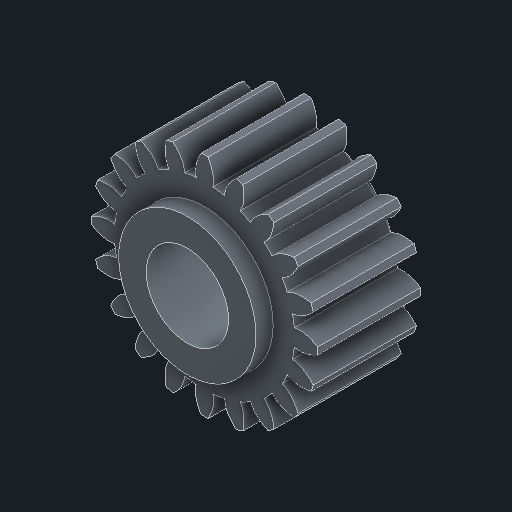
# Autodesk Inventor part: G1
Saved by Autodesk Inventor 2027 (Build 310192000, 192)
## iProperties
Created: 2026-11-10
Part Number: G1
Material: Genérico
Description: Engrenagem G1
Document SubType Name: Modeling
Designer: Bruno Madela
Mass: 9.65709 g
Surface Area: 51.8359 cm^2
Volume: 9.65709 cm^3
Density: 1 g/cm^3
Appearance: Aço
Author: Bruno Madela
Autodesk Inventor part; units mm, degrees
ref_plane "YZ Plane" through (0, 0, 0) normal (1, 0, 0) x (0, 1, 0)
ref_plane "XZ Plane" through (0, 0, 0) normal (0, 1, 0) x (-1, 0, 0)
sketch "Esboço1" plane through (0, 0, 0) normal (0, 0, 1) x (1, 0, 0)
  circle A0 centre (0, 0) radius 10
  dimension "d0" = 20
  constraints: 1 centre point
  measures "d0" diameter of A0
extrude "Extrusão1" add sketch "Esboço1" along normal blind 20
ref_plane "Plano de trabalho1" through (0, 0, 2.5) normal (0, 0, 1) x (1, 0, 0)
sketch "Esboço2" plane through (0, 0, 2.5) normal (0, 0, 1) x (1, 0, 0)
  spline S0 degree 4 poles (13.0677, -1.2247) (13.1346, -1.232) (13.263, -1.2459) (13.4395, -1.2641) (13.6431, -1.283) (13.8156, -1.2967) (13.9593, -1.3052) (14.0776, -1.3089) (14.1764, -1.3079) (14.2635, -1.3028) (14.3466, -1.2941) (14.432, -1.2822) (14.5223, -1.2675) (14.6167, -1.2504) (14.7127, -1.2311) (14.8076, -1.2098) (14.9005, -1.1865) (14.9917, -1.1614) (15.0824, -1.1345) (15.1735, -1.1058) (15.2655, -1.0755) (15.3579, -1.0435) (15.4503, -1.01) (15.5422, -0.9749) (15.6336, -0.9383) (15.7246, -0.9003) (15.8154, -0.8608) (15.9062, -0.8199) (15.9969, -0.7776) (16.0875, -0.734) (16.1779, -0.689) (16.268, -0.6427) (16.3578, -0.5952) (16.4249, -0.5585) (16.4695, -0.5336) (16.4918, -0.5211) knots 0 0 0 0 0 0.03125 0.0625 0.09375 0.125 0.15625 0.1875 0.21875 0.25 0.28125 0.3125 0.34375 0.375 0.40625 0.4375 0.46875 0.5 0.53125 0.5625 0.59375 0.625 0.65625 0.6875 0.71875 0.75 0.78125 0.8125 0.84375 0.875 0.90625 0.9375 0.96875 1 1 1 1 1
  spline S1 degree 4 poles (16.4918, 0.5211) (16.4694, 0.5337) (16.4247, 0.5588) (16.3574, 0.5959) (16.2674, 0.6439) (16.177, 0.6906) (16.0864, 0.736) (15.9956, 0.78) (15.9046, 0.8227) (15.8137, 0.864) (15.7227, 0.9038) (15.6315, 0.9422) (15.5399, 0.9791) (15.4478, 1.0145) (15.3552, 1.0483) (15.2626, 1.0806) (15.1705, 1.1112) (15.0792, 1.1401) (14.9884, 1.1672) (14.897, 1.1926) (14.8041, 1.2161) (14.709, 1.2376) (14.6129, 1.257) (14.5184, 1.2742) (14.4279, 1.289) (14.3423, 1.3011) (14.259, 1.3101) (14.172, 1.3153) (14.0733, 1.3162) (13.9553, 1.3122) (13.8122, 1.3029) (13.6403, 1.2881) (13.4377, 1.2675) (13.262, 1.2478) (13.1343, 1.2327) (13.0677, 1.2247) knots 0 0 0 0 0 0.03125 0.0625 0.09375 0.125 0.15625 0.1875 0.21875 0.25 0.28125 0.3125 0.34375 0.375 0.40625 0.4375 0.46875 0.5 0.53125 0.5625 0.59375 0.625 0.65625 0.6875 0.71875 0.75 0.78125 0.8125 0.84375 0.875 0.90625 0.9375 0.96875 1 1 1 1 1
  spline S2 degree 4 poles (12.8066, 2.8734) (12.8723, 2.8863) (12.9985, 2.9114) (13.1716, 2.9468) (13.3706, 2.9898) (13.5386, 3.0287) (13.6775, 3.0641) (13.7909, 3.0968) (13.8844, 3.1282) (13.9656, 3.1602) (14.0419, 3.1945) (14.1195, 3.2325) (14.201, 3.2746) (14.2857, 3.3202) (14.371, 3.3684) (14.4548, 3.4182) (14.5359, 3.4693) (14.615, 3.5216) (14.693, 3.5756) (14.7709, 3.6313) (14.849, 3.6889) (14.9272, 3.7481) (15.0047, 3.8089) (15.0815, 3.871) (15.1572, 3.9344) (15.2321, 3.9991) (15.3064, 4.0651) (15.3802, 4.1325) (15.4535, 4.2012) (15.5263, 4.2711) (15.5985, 4.3422) (15.6701, 4.4146) (15.7409, 4.4881) (15.7935, 4.544) (15.8283, 4.5817) (15.8456, 4.6007) knots 0 0 0 0 0 0.03125 0.0625 0.09375 0.125 0.15625 0.1875 0.21875 0.25 0.28125 0.3125 0.34375 0.375 0.40625 0.4375 0.46875 0.5 0.53125 0.5625 0.59375 0.625 0.65625 0.6875 0.71875 0.75 0.78125 0.8125 0.84375 0.875 0.90625 0.9375 0.96875 1 1 1 1 1
  spline S3 degree 4 poles (15.5236, 5.5918) (15.4984, 5.5969) (15.4481, 5.607) (15.3727, 5.6214) (15.2723, 5.6393) (15.1719, 5.6558) (15.0717, 5.6709) (14.9717, 5.6847) (14.872, 5.6972) (14.7728, 5.7083) (14.6739, 5.7181) (14.5753, 5.7264) (14.4768, 5.7332) (14.3783, 5.7384) (14.2798, 5.7419) (14.1818, 5.744) (14.0847, 5.7446) (13.9889, 5.7439) (13.8942, 5.7417) (13.7995, 5.7376) (13.7038, 5.7311) (13.6068, 5.7222) (13.5094, 5.711) (13.4141, 5.6981) (13.3235, 5.6842) (13.2383, 5.6693) (13.1564, 5.6521) (13.072, 5.6301) (12.9778, 5.6005) (12.8668, 5.5602) (12.7336, 5.5072) (12.5747, 5.44) (12.3883, 5.3579) (12.2273, 5.2848) (12.1105, 5.2311) (12.0497, 5.2029) knots 0 0 0 0 0 0.03125 0.0625 0.09375 0.125 0.15625 0.1875 0.21875 0.25 0.28125 0.3125 0.34375 0.375 0.40625 0.4375 0.46875 0.5 0.53125 0.5625 0.59375 0.625 0.65625 0.6875 0.71875 0.75 0.78125 0.8125 0.84375 0.875 0.90625 0.9375 0.96875 1 1 1 1 1
  spline S4 degree 4 poles (11.2919, 6.6902) (11.3504, 6.7228) (11.4626, 6.7856) (11.6164, 6.8728) (11.7924, 6.9751) (11.9402, 7.0641) (12.0614, 7.1406) (12.1592, 7.2067) (12.2384, 7.2655) (12.3058, 7.3209) (12.3678, 7.3771) (12.4299, 7.4372) (12.4944, 7.5025) (12.5608, 7.572) (12.6271, 7.6442) (12.6914, 7.7174) (12.7528, 7.7911) (12.8118, 7.8653) (12.8693, 7.9407) (12.9262, 8.0178) (12.9827, 8.0967) (13.0386, 8.1772) (13.0937, 8.259) (13.1474, 8.3418) (13.1998, 8.4255) (13.251, 8.5102) (13.3013, 8.5959) (13.3506, 8.6828) (13.3991, 8.7708) (13.4467, 8.8598) (13.4934, 8.9498) (13.539, 9.0408) (13.5836, 9.1326) (13.6163, 9.2021) (13.6378, 9.2487) (13.6484, 9.2721) knots 0 0 0 0 0 0.03125 0.0625 0.09375 0.125 0.15625 0.1875 0.21875 0.25 0.28125 0.3125 0.34375 0.375 0.40625 0.4375 0.46875 0.5 0.53125 0.5625 0.59375 0.625 0.65625 0.6875 0.71875 0.75 0.78125 0.8125 0.84375 0.875 0.90625 0.9375 0.96875 1 1 1 1 1
  spline S5 degree 4 poles (13.0358, 10.1152) (13.0103, 10.1123) (12.9594, 10.1063) (12.8833, 10.0967) (12.7823, 10.0826) (12.6818, 10.0673) (12.5818, 10.0507) (12.4825, 10.0329) (12.3839, 10.014) (12.2861, 9.9939) (12.1891, 9.9726) (12.0928, 9.9501) (11.9971, 9.926) (11.9018, 9.9005) (11.807, 9.8735) (11.7132, 9.8451) (11.6208, 9.8157) (11.5299, 9.7854) (11.4405, 9.754) (11.3517, 9.7208) (11.2628, 9.6851) (11.1733, 9.6466) (11.0841, 9.6059) (10.9975, 9.5642) (10.9156, 9.5229) (10.8393, 9.4824) (10.7667, 9.4407) (10.6932, 9.3937) (10.6129, 9.3364) (10.5197, 9.2638) (10.4092, 9.1722) (10.2788, 9.0593) (10.1267, 8.9237) (9.996, 8.8045) (9.9014, 8.7173) (9.8522, 8.6718) knots 0 0 0 0 0 0.03125 0.0625 0.09375 0.125 0.15625 0.1875 0.21875 0.25 0.28125 0.3125 0.34375 0.375 0.40625 0.4375 0.46875 0.5 0.53125 0.5625 0.59375 0.625 0.65625 0.6875 0.71875 0.75 0.78125 0.8125 0.84375 0.875 0.90625 0.9375 0.96875 1 1 1 1 1
  spline S6 degree 4 poles (8.6718, 9.8522) (8.7174, 9.9012) (8.8047, 9.9956) (8.9239, 10.126) (9.0596, 10.2778) (9.1727, 10.408) (9.2643, 10.5183) (9.3368, 10.6114) (9.3941, 10.6917) (9.441, 10.7653) (9.4827, 10.8379) (9.5232, 10.9143) (9.5644, 10.9963) (9.606, 11.0829) (9.6468, 11.1721) (9.6853, 11.2616) (9.7209, 11.3506) (9.7541, 11.4394) (9.7855, 11.5289) (9.8158, 11.6198) (9.8452, 11.7123) (9.8735, 11.8062) (9.9006, 11.901) (9.9261, 11.9963) (9.9501, 12.0921) (9.9726, 12.1885) (9.9939, 12.2856) (10.014, 12.3834) (10.0329, 12.4821) (10.0507, 12.5815) (10.0673, 12.6815) (10.0826, 12.7821) (10.0967, 12.8832) (10.1063, 12.9594) (10.1123, 13.0103) (10.1152, 13.0358) knots 0 0 0 0 0 0.03125 0.0625 0.09375 0.125 0.15625 0.1875 0.21875 0.25 0.28125 0.3125 0.34375 0.375 0.40625 0.4375 0.46875 0.5 0.53125 0.5625 0.59375 0.625 0.65625 0.6875 0.71875 0.75 0.78125 0.8125 0.84375 0.875 0.90625 0.9375 0.96875 1 1 1 1 1
  spline S7 degree 4 poles (9.2721, 13.6484) (9.2487, 13.6378) (9.2021, 13.6164) (9.1325, 13.5837) (9.0407, 13.5391) (8.9498, 13.4935) (8.8598, 13.4468) (8.7707, 13.3992) (8.6827, 13.3508) (8.5958, 13.3014) (8.5101, 13.2512) (8.4254, 13.2) (8.3417, 13.1476) (8.2588, 13.0939) (8.177, 13.0389) (8.0965, 12.9829) (8.0176, 12.9264) (7.9405, 12.8695) (7.8651, 12.812) (7.7909, 12.753) (7.7173, 12.6916) (7.644, 12.6274) (7.5718, 12.561) (7.5023, 12.4946) (7.4371, 12.4301) (7.377, 12.368) (7.3208, 12.3059) (7.2654, 12.2385) (7.2067, 12.1592) (7.1406, 12.0614) (7.064, 11.9401) (6.9751, 11.7923) (6.8728, 11.6164) (6.7856, 11.4626) (6.7228, 11.3504) (6.6902, 11.2919) knots 0 0 0 0 0 0.03125 0.0625 0.09375 0.125 0.15625 0.1875 0.21875 0.25 0.28125 0.3125 0.34375 0.375 0.40625 0.4375 0.46875 0.5 0.53125 0.5625 0.59375 0.625 0.65625 0.6875 0.71875 0.75 0.78125 0.8125 0.84375 0.875 0.90625 0.9375 0.96875 1 1 1 1 1
  spline S8 degree 4 poles (5.2029, 12.0497) (5.2311, 12.1104) (5.285, 12.2272) (5.3582, 12.388) (5.4404, 12.5742) (5.5077, 12.733) (5.5608, 12.8662) (5.6011, 12.9771) (5.6307, 13.0713) (5.6526, 13.1557) (5.6698, 13.2376) (5.6848, 13.3228) (5.6986, 13.4135) (5.7115, 13.5088) (5.7227, 13.6062) (5.7316, 13.7032) (5.738, 13.7989) (5.7421, 13.8936) (5.7443, 13.9884) (5.7451, 14.0842) (5.7444, 14.1813) (5.7423, 14.2793) (5.7387, 14.3779) (5.7335, 14.4764) (5.7267, 14.575) (5.7184, 14.6736) (5.7086, 14.7725) (5.6974, 14.8718) (5.6849, 14.9715) (5.6711, 15.0715) (5.6559, 15.1718) (5.6393, 15.2722) (5.6215, 15.3727) (5.607, 15.4481) (5.597, 15.4984) (5.5918, 15.5236) knots 0 0 0 0 0 0.03125 0.0625 0.09375 0.125 0.15625 0.1875 0.21875 0.25 0.28125 0.3125 0.34375 0.375 0.40625 0.4375 0.46875 0.5 0.53125 0.5625 0.59375 0.625 0.65625 0.6875 0.71875 0.75 0.78125 0.8125 0.84375 0.875 0.90625 0.9375 0.96875 1 1 1 1 1
  spline S9 degree 4 poles (4.6007, 15.8456) (4.5817, 15.8283) (4.544, 15.7935) (4.488, 15.741) (4.4145, 15.6702) (4.3421, 15.5987) (4.2709, 15.5265) (4.2009, 15.4537) (4.1322, 15.3804) (4.0648, 15.3067) (3.9988, 15.2325) (3.9341, 15.1576) (3.8707, 15.0819) (3.8085, 15.0052) (3.7477, 14.9276) (3.6884, 14.8495) (3.6309, 14.7714) (3.5751, 14.6934) (3.5212, 14.6154) (3.4689, 14.5364) (3.4178, 14.4552) (3.368, 14.3715) (3.3198, 14.2861) (3.2742, 14.2014) (3.2322, 14.1199) (3.1942, 14.0422) (3.16, 13.9658) (3.1281, 13.8846) (3.0968, 13.791) (3.0641, 13.6776) (3.0288, 13.5386) (2.9898, 13.3706) (2.9468, 13.1716) (2.9114, 12.9984) (2.8863, 12.8723) (2.8734, 12.8066) knots 0 0 0 0 0 0.03125 0.0625 0.09375 0.125 0.15625 0.1875 0.21875 0.25 0.28125 0.3125 0.34375 0.375 0.40625 0.4375 0.46875 0.5 0.53125 0.5625 0.59375 0.625 0.65625 0.6875 0.71875 0.75 0.78125 0.8125 0.84375 0.875 0.90625 0.9375 0.96875 1 1 1 1 1
  spline S10 degree 4 poles (1.2247, 13.0677) (1.2328, 13.1342) (1.2479, 13.2619) (1.2678, 13.4375) (1.2885, 13.64) (1.3035, 13.8117) (1.3129, 13.9548) (1.3169, 14.0728) (1.316, 14.1715) (1.3108, 14.2585) (1.3018, 14.3418) (1.2897, 14.4274) (1.2749, 14.5179) (1.2577, 14.6125) (1.2382, 14.7086) (1.2167, 14.8037) (1.1933, 14.8967) (1.1679, 14.988) (1.1407, 15.0789) (1.1117, 15.1702) (1.0811, 15.2623) (1.0488, 15.3549) (1.015, 15.4475) (0.9796, 15.5397) (0.9426, 15.6313) (0.9042, 15.7225) (0.8643, 15.8135) (0.823, 15.9045) (0.7803, 15.9955) (0.7362, 16.0863) (0.6908, 16.177) (0.644, 16.2673) (0.5959, 16.3574) (0.5589, 16.4247) (0.5338, 16.4694) (0.5211, 16.4918) knots 0 0 0 0 0 0.03125 0.0625 0.09375 0.125 0.15625 0.1875 0.21875 0.25 0.28125 0.3125 0.34375 0.375 0.40625 0.4375 0.46875 0.5 0.53125 0.5625 0.59375 0.625 0.65625 0.6875 0.71875 0.75 0.78125 0.8125 0.84375 0.875 0.90625 0.9375 0.96875 1 1 1 1 1
  spline S11 degree 4 poles (-0.5211, 16.4918) (-0.5338, 16.4694) (-0.5589, 16.4247) (-0.5959, 16.3574) (-0.644, 16.2674) (-0.6908, 16.177) (-0.7362, 16.0863) (-0.7803, 15.9955) (-0.823, 15.9046) (-0.8643, 15.8136) (-0.9042, 15.7226) (-0.9427, 15.6314) (-0.9796, 15.5397) (-1.015, 15.4476) (-1.0489, 15.355) (-1.0811, 15.2624) (-1.1118, 15.1703) (-1.1407, 15.079) (-1.1679, 14.9881) (-1.1933, 14.8968) (-1.2168, 14.8038) (-1.2383, 14.7088) (-1.2577, 14.6126) (-1.2749, 14.5181) (-1.2897, 14.4275) (-1.3018, 14.3419) (-1.3107, 14.2587) (-1.316, 14.1716) (-1.3168, 14.0729) (-1.3128, 13.9549) (-1.3034, 13.8118) (-1.2885, 13.64) (-1.2678, 13.4375) (-1.2479, 13.2619) (-1.2327, 13.1342) (-1.2247, 13.0677) knots 0 0 0 0 0 0.03125 0.0625 0.09375 0.125 0.15625 0.1875 0.21875 0.25 0.28125 0.3125 0.34375 0.375 0.40625 0.4375 0.46875 0.5 0.53125 0.5625 0.59375 0.625 0.65625 0.6875 0.71875 0.75 0.78125 0.8125 0.84375 0.875 0.90625 0.9375 0.96875 1 1 1 1 1
  spline S12 degree 4 poles (-2.8734, 12.8066) (-2.8863, 12.8723) (-2.9113, 12.9985) (-2.9466, 13.1716) (-2.9895, 13.3707) (-3.0283, 13.5387) (-3.0636, 13.6776) (-3.0962, 13.7911) (-3.1276, 13.8847) (-3.1594, 13.9659) (-3.1937, 14.0423) (-3.2317, 14.1199) (-3.2737, 14.2014) (-3.3193, 14.2861) (-3.3675, 14.3715) (-3.4173, 14.4552) (-3.4684, 14.5364) (-3.5207, 14.6154) (-3.5747, 14.6934) (-3.6304, 14.7714) (-3.688, 14.8495) (-3.7473, 14.9276) (-3.8082, 15.0052) (-3.8703, 15.0819) (-3.9338, 15.1576) (-3.9985, 15.2324) (-4.0646, 15.3067) (-4.132, 15.3804) (-4.2007, 15.4537) (-4.2707, 15.5265) (-4.342, 15.5987) (-4.4144, 15.6702) (-4.4879, 15.741) (-4.544, 15.7935) (-4.5817, 15.8283) (-4.6007, 15.8456) knots 0 0 0 0 0 0.03125 0.0625 0.09375 0.125 0.15625 0.1875 0.21875 0.25 0.28125 0.3125 0.34375 0.375 0.40625 0.4375 0.46875 0.5 0.53125 0.5625 0.59375 0.625 0.65625 0.6875 0.71875 0.75 0.78125 0.8125 0.84375 0.875 0.90625 0.9375 0.96875 1 1 1 1 1
  spline S13 degree 4 poles (-5.5918, 15.5236) (-5.597, 15.4984) (-5.607, 15.4481) (-5.6215, 15.3727) (-5.6394, 15.2722) (-5.656, 15.1718) (-5.6712, 15.0715) (-5.685, 14.9715) (-5.6975, 14.8718) (-5.7087, 14.7725) (-5.7185, 14.6736) (-5.7269, 14.575) (-5.7337, 14.4765) (-5.7389, 14.3779) (-5.7425, 14.2794) (-5.7446, 14.1813) (-5.7453, 14.0843) (-5.7446, 13.9885) (-5.7424, 13.8937) (-5.7383, 13.7989) (-5.7319, 13.7033) (-5.7229, 13.6062) (-5.7117, 13.5088) (-5.6988, 13.4135) (-5.6849, 13.3229) (-5.67, 13.2377) (-5.6528, 13.1558) (-5.6308, 13.0713) (-5.6012, 12.9772) (-5.5608, 12.8662) (-5.5077, 12.733) (-5.4404, 12.5743) (-5.3582, 12.3881) (-5.285, 12.2272) (-5.2311, 12.1105) (-5.2029, 12.0497) knots 0 0 0 0 0 0.03125 0.0625 0.09375 0.125 0.15625 0.1875 0.21875 0.25 0.28125 0.3125 0.34375 0.375 0.40625 0.4375 0.46875 0.5 0.53125 0.5625 0.59375 0.625 0.65625 0.6875 0.71875 0.75 0.78125 0.8125 0.84375 0.875 0.90625 0.9375 0.96875 1 1 1 1 1
  spline S14 degree 4 poles (-6.6902, 11.2919) (-6.7228, 11.3504) (-6.7855, 11.4626) (-6.8726, 11.6164) (-6.9749, 11.7924) (-7.0637, 11.9402) (-7.1402, 12.0615) (-7.2063, 12.1593) (-7.265, 12.2386) (-7.3204, 12.3059) (-7.3766, 12.368) (-7.4367, 12.4301) (-7.5019, 12.4947) (-7.5715, 12.5611) (-7.6437, 12.6274) (-7.7169, 12.6917) (-7.7906, 12.7531) (-7.8648, 12.8121) (-7.9402, 12.8696) (-8.0173, 12.9265) (-8.0963, 12.983) (-8.1768, 13.0389) (-8.2586, 13.0939) (-8.3414, 13.1476) (-8.4252, 13.2001) (-8.5099, 13.2513) (-8.5957, 13.3015) (-8.6826, 13.3508) (-8.7706, 13.3992) (-8.8597, 13.4468) (-8.9497, 13.4935) (-9.0407, 13.5391) (-9.1325, 13.5837) (-9.202, 13.6164) (-9.2487, 13.6378) (-9.2721, 13.6484) knots 0 0 0 0 0 0.03125 0.0625 0.09375 0.125 0.15625 0.1875 0.21875 0.25 0.28125 0.3125 0.34375 0.375 0.40625 0.4375 0.46875 0.5 0.53125 0.5625 0.59375 0.625 0.65625 0.6875 0.71875 0.75 0.78125 0.8125 0.84375 0.875 0.90625 0.9375 0.96875 1 1 1 1 1
  spline S15 degree 4 poles (-10.1152, 13.0358) (-10.1123, 13.0103) (-10.1063, 12.9593) (-10.0968, 12.8831) (-10.0827, 12.782) (-10.0675, 12.6814) (-10.0509, 12.5814) (-10.0332, 12.482) (-10.0143, 12.3833) (-9.9943, 12.2854) (-9.973, 12.1883) (-9.9505, 12.092) (-9.9265, 11.9961) (-9.901, 11.9008) (-9.874, 11.806) (-9.8457, 11.7121) (-9.8163, 11.6196) (-9.786, 11.5287) (-9.7546, 11.4392) (-9.7215, 11.3504) (-9.6858, 11.2614) (-9.6474, 11.1718) (-9.6066, 11.0827) (-9.5649, 10.996) (-9.5236, 10.9141) (-9.4831, 10.8377) (-9.4414, 10.7651) (-9.3945, 10.6916) (-9.3372, 10.6112) (-9.2645, 10.5181) (-9.1729, 10.4079) (-9.0598, 10.2777) (-8.924, 10.126) (-8.8047, 9.9956) (-8.7174, 9.9012) (-8.6718, 9.8522) knots 0 0 0 0 0 0.03125 0.0625 0.09375 0.125 0.15625 0.1875 0.21875 0.25 0.28125 0.3125 0.34375 0.375 0.40625 0.4375 0.46875 0.5 0.53125 0.5625 0.59375 0.625 0.65625 0.6875 0.71875 0.75 0.78125 0.8125 0.84375 0.875 0.90625 0.9375 0.96875 1 1 1 1 1
  spline S16 degree 4 poles (-9.8522, 8.6718) (-9.9012, 8.7174) (-9.9956, 8.8048) (-10.1259, 8.9241) (-10.2776, 9.0599) (-10.4077, 9.1729) (-10.518, 9.2646) (-10.6111, 9.3372) (-10.6914, 9.3945) (-10.7649, 9.4414) (-10.8376, 9.4831) (-10.9139, 9.5236) (-10.9959, 9.5648) (-11.0825, 9.6065) (-11.1717, 9.6473) (-11.2612, 9.6857) (-11.3503, 9.7214) (-11.4391, 9.7546) (-11.5286, 9.786) (-11.6195, 9.8162) (-11.712, 9.8456) (-11.8059, 9.8739) (-11.9007, 9.9009) (-11.9961, 9.9265) (-12.0919, 9.9504) (-12.1883, 9.973) (-12.2854, 9.9942) (-12.3833, 10.0142) (-12.4819, 10.0331) (-12.5814, 10.0509) (-12.6814, 10.0674) (-12.782, 10.0827) (-12.8831, 10.0968) (-12.9593, 10.1063) (-13.0103, 10.1123) (-13.0358, 10.1152) knots 0 0 0 0 0 0.03125 0.0625 0.09375 0.125 0.15625 0.1875 0.21875 0.25 0.28125 0.3125 0.34375 0.375 0.40625 0.4375 0.46875 0.5 0.53125 0.5625 0.59375 0.625 0.65625 0.6875 0.71875 0.75 0.78125 0.8125 0.84375 0.875 0.90625 0.9375 0.96875 1 1 1 1 1
  spline S17 degree 4 poles (-13.6484, 9.2721) (-13.6378, 9.2487) (-13.6164, 9.2021) (-13.5837, 9.1326) (-13.5391, 9.0407) (-13.4935, 8.9498) (-13.4468, 8.8598) (-13.3993, 8.7707) (-13.3508, 8.6828) (-13.3015, 8.5959) (-13.2513, 8.5101) (-13.2001, 8.4254) (-13.1477, 8.3417) (-13.0939, 8.2589) (-13.0389, 8.1771) (-12.983, 8.0966) (-12.9265, 8.0177) (-12.8696, 7.9406) (-12.8121, 7.8652) (-12.7531, 7.791) (-12.6917, 7.7174) (-12.6274, 7.6441) (-12.5611, 7.5719) (-12.4947, 7.5024) (-12.4301, 7.4372) (-12.368, 7.3771) (-12.3059, 7.321) (-12.2385, 7.2656) (-12.1592, 7.2068) (-12.0613, 7.1407) (-11.9401, 7.0642) (-11.7923, 6.9752) (-11.6163, 6.8729) (-11.4626, 6.7856) (-11.3504, 6.7228) (-11.2919, 6.6902) knots 0 0 0 0 0 0.03125 0.0625 0.09375 0.125 0.15625 0.1875 0.21875 0.25 0.28125 0.3125 0.34375 0.375 0.40625 0.4375 0.46875 0.5 0.53125 0.5625 0.59375 0.625 0.65625 0.6875 0.71875 0.75 0.78125 0.8125 0.84375 0.875 0.90625 0.9375 0.96875 1 1 1 1 1
  spline S18 degree 4 poles (-12.0497, 5.2029) (-12.1104, 5.2311) (-12.2272, 5.285) (-12.3881, 5.3581) (-12.5743, 5.4403) (-12.733, 5.5076) (-12.8662, 5.5607) (-12.9772, 5.601) (-13.0713, 5.6306) (-13.1557, 5.6526) (-13.2377, 5.6698) (-13.3228, 5.6847) (-13.4135, 5.6986) (-13.5088, 5.7114) (-13.6062, 5.7227) (-13.7032, 5.7316) (-13.7989, 5.738) (-13.8937, 5.7421) (-13.9884, 5.7443) (-14.0843, 5.745) (-14.1813, 5.7443) (-14.2794, 5.7423) (-14.3779, 5.7387) (-14.4765, 5.7335) (-14.575, 5.7267) (-14.6736, 5.7183) (-14.7725, 5.7085) (-14.8718, 5.6974) (-14.9715, 5.6849) (-15.0715, 5.671) (-15.1718, 5.6559) (-15.2722, 5.6393) (-15.3727, 5.6215) (-15.4481, 5.607) (-15.4984, 5.597) (-15.5236, 5.5918) knots 0 0 0 0 0 0.03125 0.0625 0.09375 0.125 0.15625 0.1875 0.21875 0.25 0.28125 0.3125 0.34375 0.375 0.40625 0.4375 0.46875 0.5 0.53125 0.5625 0.59375 0.625 0.65625 0.6875 0.71875 0.75 0.78125 0.8125 0.84375 0.875 0.90625 0.9375 0.96875 1 1 1 1 1
  spline S19 degree 4 poles (-15.8456, 4.6007) (-15.8283, 4.5817) (-15.7935, 4.544) (-15.741, 4.488) (-15.6702, 4.4145) (-15.5987, 4.3421) (-15.5265, 4.2709) (-15.4538, 4.2009) (-15.3805, 4.1322) (-15.3067, 4.0648) (-15.2325, 3.9988) (-15.1576, 3.9341) (-15.0819, 3.8706) (-15.0052, 3.8085) (-14.9276, 3.7477) (-14.8495, 3.6884) (-14.7714, 3.6308) (-14.6935, 3.5751) (-14.6155, 3.5212) (-14.5364, 3.4688) (-14.4553, 3.4178) (-14.3715, 3.368) (-14.2861, 3.3198) (-14.2015, 3.2742) (-14.1199, 3.2322) (-14.0423, 3.1942) (-13.9658, 3.16) (-13.8846, 3.1281) (-13.791, 3.0968) (-13.6776, 3.0641) (-13.5386, 3.0288) (-13.3706, 2.9899) (-13.1716, 2.9469) (-12.9984, 2.9114) (-12.8723, 2.8863) (-12.8066, 2.8734) knots 0 0 0 0 0 0.03125 0.0625 0.09375 0.125 0.15625 0.1875 0.21875 0.25 0.28125 0.3125 0.34375 0.375 0.40625 0.4375 0.46875 0.5 0.53125 0.5625 0.59375 0.625 0.65625 0.6875 0.71875 0.75 0.78125 0.8125 0.84375 0.875 0.90625 0.9375 0.96875 1 1 1 1 1
  spline S20 degree 4 poles (-13.0677, 1.2247) (-13.1342, 1.2327) (-13.2619, 1.2479) (-13.4375, 1.2677) (-13.64, 1.2883) (-13.8118, 1.3033) (-13.9548, 1.3126) (-14.0728, 1.3166) (-14.1715, 1.3157) (-14.2586, 1.3104) (-14.3419, 1.3015) (-14.4275, 1.2894) (-14.518, 1.2745) (-14.6126, 1.2573) (-14.7087, 1.2379) (-14.8037, 1.2164) (-14.8967, 1.1929) (-14.9881, 1.1676) (-15.0789, 1.1404) (-15.1703, 1.1114) (-15.2624, 1.0808) (-15.355, 1.0486) (-15.4476, 1.0147) (-15.5397, 0.9793) (-15.6313, 0.9424) (-15.7225, 0.904) (-15.8136, 0.8641) (-15.9045, 0.8228) (-15.9955, 0.7801) (-16.0863, 0.7361) (-16.177, 0.6907) (-16.2673, 0.6439) (-16.3574, 0.5959) (-16.4247, 0.5589) (-16.4694, 0.5337) (-16.4918, 0.5211) knots 0 0 0 0 0 0.03125 0.0625 0.09375 0.125 0.15625 0.1875 0.21875 0.25 0.28125 0.3125 0.34375 0.375 0.40625 0.4375 0.46875 0.5 0.53125 0.5625 0.59375 0.625 0.65625 0.6875 0.71875 0.75 0.78125 0.8125 0.84375 0.875 0.90625 0.9375 0.96875 1 1 1 1 1
  spline S21 degree 4 poles (-16.4918, -0.5211) (-16.4694, -0.5337) (-16.4247, -0.5588) (-16.3574, -0.5959) (-16.2673, -0.6439) (-16.177, -0.6906) (-16.0863, -0.736) (-15.9955, -0.78) (-15.9045, -0.8227) (-15.8135, -0.864) (-15.7225, -0.9038) (-15.6313, -0.9422) (-15.5397, -0.9791) (-15.4475, -1.0145) (-15.355, -1.0483) (-15.2624, -1.0806) (-15.1703, -1.1112) (-15.0789, -1.1401) (-14.9881, -1.1673) (-14.8967, -1.1926) (-14.8037, -1.2161) (-14.7087, -1.2376) (-14.6126, -1.257) (-14.518, -1.2743) (-14.4275, -1.2891) (-14.3419, -1.3012) (-14.2586, -1.3102) (-14.1715, -1.3154) (-14.0729, -1.3164) (-13.9549, -1.3124) (-13.8118, -1.3031) (-13.64, -1.2882) (-13.4375, -1.2676) (-13.2619, -1.2478) (-13.1342, -1.2327) (-13.0677, -1.2247) knots 0 0 0 0 0 0.03125 0.0625 0.09375 0.125 0.15625 0.1875 0.21875 0.25 0.28125 0.3125 0.34375 0.375 0.40625 0.4375 0.46875 0.5 0.53125 0.5625 0.59375 0.625 0.65625 0.6875 0.71875 0.75 0.78125 0.8125 0.84375 0.875 0.90625 0.9375 0.96875 1 1 1 1 1
  spline S22 degree 4 poles (-12.8066, -2.8734) (-12.8723, -2.8863) (-12.9985, -2.9113) (-13.1716, -2.9466) (-13.3706, -2.9895) (-13.5386, -3.0283) (-13.6776, -3.0636) (-13.791, -3.0962) (-13.8846, -3.1276) (-13.9658, -3.1595) (-14.0422, -3.1937) (-14.1198, -3.2317) (-14.2013, -3.2738) (-14.286, -3.3194) (-14.3714, -3.3676) (-14.4551, -3.4174) (-14.5363, -3.4685) (-14.6153, -3.5208) (-14.6933, -3.5748) (-14.7713, -3.6305) (-14.8494, -3.6881) (-14.9275, -3.7474) (-15.0051, -3.8082) (-15.0818, -3.8704) (-15.1575, -3.9338) (-15.2324, -3.9986) (-15.3066, -4.0646) (-15.3804, -4.132) (-15.4537, -4.2008) (-15.5265, -4.2708) (-15.5987, -4.342) (-15.6702, -4.4144) (-15.741, -4.4879) (-15.7935, -4.544) (-15.8283, -4.5817) (-15.8456, -4.6007) knots 0 0 0 0 0 0.03125 0.0625 0.09375 0.125 0.15625 0.1875 0.21875 0.25 0.28125 0.3125 0.34375 0.375 0.40625 0.4375 0.46875 0.5 0.53125 0.5625 0.59375 0.625 0.65625 0.6875 0.71875 0.75 0.78125 0.8125 0.84375 0.875 0.90625 0.9375 0.96875 1 1 1 1 1
  spline S23 degree 4 poles (-15.5236, -5.5918) (-15.4984, -5.597) (-15.4481, -5.607) (-15.3727, -5.6215) (-15.2722, -5.6393) (-15.1718, -5.6559) (-15.0715, -5.6711) (-14.9715, -5.6849) (-14.8718, -5.6974) (-14.7725, -5.7086) (-14.6736, -5.7184) (-14.575, -5.7267) (-14.4765, -5.7335) (-14.3779, -5.7387) (-14.2794, -5.7423) (-14.1813, -5.7444) (-14.0843, -5.745) (-13.9885, -5.7443) (-13.8937, -5.7421) (-13.7989, -5.738) (-13.7033, -5.7316) (-13.6062, -5.7227) (-13.5088, -5.7115) (-13.4135, -5.6986) (-13.3229, -5.6847) (-13.2377, -5.6698) (-13.1558, -5.6526) (-13.0713, -5.6307) (-12.9772, -5.601) (-12.8662, -5.5607) (-12.733, -5.5076) (-12.5743, -5.4404) (-12.3881, -5.3581) (-12.2272, -5.285) (-12.1105, -5.2311) (-12.0497, -5.2029) knots 0 0 0 0 0 0.03125 0.0625 0.09375 0.125 0.15625 0.1875 0.21875 0.25 0.28125 0.3125 0.34375 0.375 0.40625 0.4375 0.46875 0.5 0.53125 0.5625 0.59375 0.625 0.65625 0.6875 0.71875 0.75 0.78125 0.8125 0.84375 0.875 0.90625 0.9375 0.96875 1 1 1 1 1
  spline S24 degree 4 poles (-11.2919, -6.6902) (-11.3504, -6.7229) (-11.4627, -6.7857) (-11.6165, -6.873) (-11.7926, -6.9755) (-11.9404, -7.0645) (-12.0617, -7.141) (-12.1596, -7.2071) (-12.2389, -7.2658) (-12.3063, -7.3212) (-12.3684, -7.3774) (-12.4305, -7.4374) (-12.495, -7.5026) (-12.5614, -7.5721) (-12.6277, -7.6443) (-12.692, -7.7175) (-12.7534, -7.7911) (-12.8124, -7.8653) (-12.8699, -7.9407) (-12.9267, -8.0178) (-12.9832, -8.0967) (-13.0392, -8.1772) (-13.0942, -8.259) (-13.1479, -8.3418) (-13.2003, -8.4255) (-13.2515, -8.5102) (-13.3016, -8.5959) (-13.3509, -8.6828) (-13.3994, -8.7708) (-13.4469, -8.8598) (-13.4936, -8.9498) (-13.5392, -9.0408) (-13.5837, -9.1326) (-13.6164, -9.2021) (-13.6378, -9.2487) (-13.6484, -9.2721) knots 0 0 0 0 0 0.03125 0.0625 0.09375 0.125 0.15625 0.1875 0.21875 0.25 0.28125 0.3125 0.34375 0.375 0.40625 0.4375 0.46875 0.5 0.53125 0.5625 0.59375 0.625 0.65625 0.6875 0.71875 0.75 0.78125 0.8125 0.84375 0.875 0.90625 0.9375 0.96875 1 1 1 1 1
  spline S25 degree 4 poles (-13.0358, -10.1152) (-13.0103, -10.1123) (-12.9593, -10.1063) (-12.8831, -10.0966) (-12.782, -10.0825) (-12.6814, -10.0671) (-12.5814, -10.0505) (-12.482, -10.0327) (-12.3833, -10.0138) (-12.2854, -9.9937) (-12.1884, -9.9724) (-12.092, -9.9498) (-11.9961, -9.9258) (-11.9008, -9.9003) (-11.806, -9.8732) (-11.7121, -9.8449) (-11.6196, -9.8155) (-11.5287, -9.7852) (-11.4392, -9.7539) (-11.3504, -9.7207) (-11.2614, -9.6851) (-11.1718, -9.6467) (-11.0826, -9.6059) (-10.996, -9.5643) (-10.914, -9.5232) (-10.8376, -9.4828) (-10.765, -9.4413) (-10.6914, -9.3945) (-10.6111, -9.3373) (-10.518, -9.2648) (-10.4077, -9.1732) (-10.2776, -9.0601) (-10.1259, -8.9243) (-9.9955, -8.8049) (-9.9012, -8.7175) (-9.8522, -8.6718) knots 0 0 0 0 0 0.03125 0.0625 0.09375 0.125 0.15625 0.1875 0.21875 0.25 0.28125 0.3125 0.34375 0.375 0.40625 0.4375 0.46875 0.5 0.53125 0.5625 0.59375 0.625 0.65625 0.6875 0.71875 0.75 0.78125 0.8125 0.84375 0.875 0.90625 0.9375 0.96875 1 1 1 1 1
  spline S26 degree 4 poles (-8.6718, -9.8522) (-8.7174, -9.9013) (-8.8047, -9.9959) (-8.9239, -10.1266) (-9.0596, -10.2785) (-9.1726, -10.4089) (-9.2643, -10.5193) (-9.3369, -10.6124) (-9.3943, -10.6928) (-9.4412, -10.7663) (-9.483, -10.8388) (-9.5235, -10.9151) (-9.5647, -10.997) (-9.6064, -11.0836) (-9.6472, -11.1728) (-9.6857, -11.2623) (-9.7213, -11.3513) (-9.7545, -11.4401) (-9.7859, -11.5295) (-9.8162, -11.6203) (-9.8456, -11.7128) (-9.8739, -11.8067) (-9.9009, -11.9014) (-9.9264, -11.9967) (-9.9504, -12.0925) (-9.973, -12.1888) (-9.9942, -12.2859) (-10.0143, -12.3837) (-10.0332, -12.4823) (-10.0509, -12.5817) (-10.0674, -12.6816) (-10.0827, -12.7822) (-10.0968, -12.8832) (-10.1063, -12.9594) (-10.1123, -13.0103) (-10.1152, -13.0358) knots 0 0 0 0 0 0.03125 0.0625 0.09375 0.125 0.15625 0.1875 0.21875 0.25 0.28125 0.3125 0.34375 0.375 0.40625 0.4375 0.46875 0.5 0.53125 0.5625 0.59375 0.625 0.65625 0.6875 0.71875 0.75 0.78125 0.8125 0.84375 0.875 0.90625 0.9375 0.96875 1 1 1 1 1
  spline S27 degree 4 poles (-9.2721, -13.6484) (-9.2487, -13.6378) (-9.202, -13.6164) (-9.1325, -13.5837) (-9.0407, -13.5391) (-8.9497, -13.4935) (-8.8597, -13.4469) (-8.7706, -13.3993) (-8.6826, -13.3509) (-8.5957, -13.3016) (-8.5099, -13.2514) (-8.4252, -13.2002) (-8.3414, -13.1478) (-8.2586, -13.0941) (-8.1768, -13.0391) (-8.0963, -12.9831) (-8.0173, -12.9266) (-7.9402, -12.8697) (-7.8649, -12.8122) (-7.7906, -12.7532) (-7.717, -12.6918) (-7.6437, -12.6276) (-7.5715, -12.5612) (-7.502, -12.4948) (-7.4368, -12.4303) (-7.3767, -12.3682) (-7.3205, -12.3061) (-7.2651, -12.2387) (-7.2064, -12.1594) (-7.1404, -12.0615) (-7.0638, -11.9402) (-6.975, -11.7925) (-6.8727, -11.6164) (-6.7855, -11.4627) (-6.7228, -11.3504) (-6.6902, -11.2919) knots 0 0 0 0 0 0.03125 0.0625 0.09375 0.125 0.15625 0.1875 0.21875 0.25 0.28125 0.3125 0.34375 0.375 0.40625 0.4375 0.46875 0.5 0.53125 0.5625 0.59375 0.625 0.65625 0.6875 0.71875 0.75 0.78125 0.8125 0.84375 0.875 0.90625 0.9375 0.96875 1 1 1 1 1
  spline S28 degree 4 poles (-5.2029, -12.0497) (-5.2311, -12.1106) (-5.2849, -12.2275) (-5.358, -12.3886) (-5.4402, -12.5751) (-5.5074, -12.7341) (-5.5606, -12.8674) (-5.6009, -12.9784) (-5.6306, -13.0726) (-5.6526, -13.157) (-5.6698, -13.2388) (-5.6848, -13.3239) (-5.6987, -13.4145) (-5.7116, -13.5098) (-5.7228, -13.6071) (-5.7317, -13.7041) (-5.7382, -13.7998) (-5.7423, -13.8945) (-5.7445, -13.9892) (-5.7452, -14.085) (-5.7445, -14.182) (-5.7425, -14.28) (-5.7389, -14.3785) (-5.7337, -14.477) (-5.7269, -14.5755) (-5.7185, -14.6741) (-5.7087, -14.7729) (-5.6975, -14.8722) (-5.685, -14.9718) (-5.6711, -15.0718) (-5.6559, -15.172) (-5.6394, -15.2723) (-5.6215, -15.3728) (-5.607, -15.4481) (-5.597, -15.4984) (-5.5918, -15.5236) knots 0 0 0 0 0 0.03125 0.0625 0.09375 0.125 0.15625 0.1875 0.21875 0.25 0.28125 0.3125 0.34375 0.375 0.40625 0.4375 0.46875 0.5 0.53125 0.5625 0.59375 0.625 0.65625 0.6875 0.71875 0.75 0.78125 0.8125 0.84375 0.875 0.90625 0.9375 0.96875 1 1 1 1 1
  spline S29 degree 4 poles (-4.6007, -15.8456) (-4.5817, -15.8283) (-4.544, -15.7935) (-4.4879, -15.741) (-4.4144, -15.6702) (-4.342, -15.5986) (-4.2708, -15.5265) (-4.2008, -15.4537) (-4.132, -15.3804) (-4.0646, -15.3066) (-3.9986, -15.2324) (-3.9338, -15.1575) (-3.8704, -15.0818) (-3.8082, -15.0051) (-3.7474, -14.9275) (-3.6881, -14.8494) (-3.6305, -14.7712) (-3.5747, -14.6933) (-3.5208, -14.6153) (-3.4684, -14.5363) (-3.4174, -14.4551) (-3.3675, -14.3714) (-3.3194, -14.286) (-3.2737, -14.2013) (-3.2317, -14.1198) (-3.1937, -14.0422) (-3.1594, -13.9658) (-3.1275, -13.8846) (-3.0962, -13.791) (-3.0636, -13.6776) (-3.0283, -13.5386) (-2.9894, -13.3706) (-2.9466, -13.1716) (-2.9112, -12.9985) (-2.8863, -12.8723) (-2.8734, -12.8066) knots 0 0 0 0 0 0.03125 0.0625 0.09375 0.125 0.15625 0.1875 0.21875 0.25 0.28125 0.3125 0.34375 0.375 0.40625 0.4375 0.46875 0.5 0.53125 0.5625 0.59375 0.625 0.65625 0.6875 0.71875 0.75 0.78125 0.8125 0.84375 0.875 0.90625 0.9375 0.96875 1 1 1 1 1
  spline S30 degree 4 poles (-1.2247, -13.0677) (-1.2327, -13.1343) (-1.2477, -13.2621) (-1.2675, -13.4379) (-1.288, -13.6406) (-1.3029, -13.8125) (-1.3122, -13.9557) (-1.3162, -14.0737) (-1.3154, -14.1724) (-1.3102, -14.2595) (-1.3013, -14.3427) (-1.2892, -14.4283) (-1.2745, -14.5188) (-1.2573, -14.6133) (-1.2379, -14.7094) (-1.2164, -14.8044) (-1.1929, -14.8974) (-1.1676, -14.9887) (-1.1404, -15.0795) (-1.1115, -15.1708) (-1.0809, -15.2629) (-1.0486, -15.3555) (-1.0148, -15.448) (-0.9794, -15.5402) (-0.9425, -15.6317) (-0.9041, -15.7229) (-0.8642, -15.8139) (-0.8229, -15.9048) (-0.7802, -15.9957) (-0.7361, -16.0865) (-0.6907, -16.1771) (-0.644, -16.2675) (-0.5959, -16.3575) (-0.5589, -16.4247) (-0.5337, -16.4694) (-0.5211, -16.4918) knots 0 0 0 0 0 0.03125 0.0625 0.09375 0.125 0.15625 0.1875 0.21875 0.25 0.28125 0.3125 0.34375 0.375 0.40625 0.4375 0.46875 0.5 0.53125 0.5625 0.59375 0.625 0.65625 0.6875 0.71875 0.75 0.78125 0.8125 0.84375 0.875 0.90625 0.9375 0.96875 1 1 1 1 1
  spline S31 degree 4 poles (0.5211, -16.4918) (0.5338, -16.4694) (0.5589, -16.4247) (0.596, -16.3574) (0.6441, -16.2674) (0.6908, -16.177) (0.7363, -16.0863) (0.7804, -15.9955) (0.8231, -15.9046) (0.8644, -15.8136) (0.9043, -15.7226) (0.9427, -15.6314) (0.9797, -15.5398) (1.0151, -15.4476) (1.049, -15.3551) (1.0813, -15.2625) (1.1119, -15.1704) (1.1409, -15.079) (1.1681, -14.9882) (1.1934, -14.8969) (1.2169, -14.8039) (1.2384, -14.7089) (1.2579, -14.6128) (1.2751, -14.5182) (1.2899, -14.4277) (1.302, -14.3422) (1.311, -14.259) (1.3162, -14.1719) (1.3171, -14.0733) (1.3131, -13.9553) (1.3037, -13.8122) (1.2887, -13.6403) (1.2679, -13.4377) (1.248, -13.262) (1.2328, -13.1343) (1.2247, -13.0677) knots 0 0 0 0 0 0.03125 0.0625 0.09375 0.125 0.15625 0.1875 0.21875 0.25 0.28125 0.3125 0.34375 0.375 0.40625 0.4375 0.46875 0.5 0.53125 0.5625 0.59375 0.625 0.65625 0.6875 0.71875 0.75 0.78125 0.8125 0.84375 0.875 0.90625 0.9375 0.96875 1 1 1 1 1
  spline S32 degree 4 poles (2.8734, -12.8066) (2.8863, -12.8723) (2.9113, -12.9984) (2.9467, -13.1716) (2.9896, -13.3706) (3.0285, -13.5386) (3.0638, -13.6776) (3.0964, -13.791) (3.1277, -13.8846) (3.1596, -13.9658) (3.1938, -14.0423) (3.2318, -14.1199) (3.2738, -14.2015) (3.3194, -14.2861) (3.3676, -14.3715) (3.4174, -14.4553) (3.4685, -14.5364) (3.5208, -14.6155) (3.5748, -14.6935) (3.6305, -14.7714) (3.6881, -14.8495) (3.7474, -14.9276) (3.8082, -15.0052) (3.8704, -15.0819) (3.9338, -15.1576) (3.9986, -15.2325) (4.0646, -15.3067) (4.132, -15.3805) (4.2007, -15.4538) (4.2708, -15.5265) (4.342, -15.5987) (4.4144, -15.6702) (4.4879, -15.741) (4.544, -15.7935) (4.5817, -15.8283) (4.6007, -15.8456) knots 0 0 0 0 0 0.03125 0.0625 0.09375 0.125 0.15625 0.1875 0.21875 0.25 0.28125 0.3125 0.34375 0.375 0.40625 0.4375 0.46875 0.5 0.53125 0.5625 0.59375 0.625 0.65625 0.6875 0.71875 0.75 0.78125 0.8125 0.84375 0.875 0.90625 0.9375 0.96875 1 1 1 1 1
  spline S33 degree 4 poles (5.5918, -15.5236) (5.597, -15.4984) (5.607, -15.4481) (5.6215, -15.3726) (5.6394, -15.2721) (5.6559, -15.1717) (5.6711, -15.0715) (5.685, -14.9714) (5.6975, -14.8717) (5.7087, -14.7724) (5.7185, -14.6735) (5.7269, -14.5749) (5.7337, -14.4764) (5.7389, -14.3778) (5.7425, -14.2793) (5.7446, -14.1812) (5.7453, -14.0841) (5.7446, -13.9883) (5.7424, -13.8935) (5.7383, -13.7988) (5.7319, -13.7031) (5.723, -13.6061) (5.7118, -13.5087) (5.6989, -13.4134) (5.685, -13.3227) (5.6701, -13.2376) (5.6529, -13.1556) (5.631, -13.0712) (5.6013, -12.9771) (5.561, -12.8661) (5.5079, -12.733) (5.4406, -12.5742) (5.3583, -12.388) (5.2851, -12.2272) (5.2311, -12.1104) (5.2029, -12.0497) knots 0 0 0 0 0 0.03125 0.0625 0.09375 0.125 0.15625 0.1875 0.21875 0.25 0.28125 0.3125 0.34375 0.375 0.40625 0.4375 0.46875 0.5 0.53125 0.5625 0.59375 0.625 0.65625 0.6875 0.71875 0.75 0.78125 0.8125 0.84375 0.875 0.90625 0.9375 0.96875 1 1 1 1 1
  spline S34 degree 4 poles (6.6902, -11.2919) (6.7228, -11.3504) (6.7856, -11.4627) (6.8728, -11.6165) (6.9752, -11.7926) (7.0641, -11.9404) (7.1407, -12.0617) (7.2068, -12.1595) (7.2655, -12.2388) (7.3209, -12.3062) (7.377, -12.3683) (7.4371, -12.4304) (7.5023, -12.4949) (7.5718, -12.5613) (7.644, -12.6277) (7.7172, -12.6919) (7.7909, -12.7533) (7.8651, -12.8123) (7.9405, -12.8698) (8.0175, -12.9267) (8.0965, -12.9832) (8.177, -13.0391) (8.2588, -13.0941) (8.3416, -13.1478) (8.4253, -13.2002) (8.51, -13.2514) (8.5958, -13.3016) (8.6827, -13.3509) (8.7707, -13.3994) (8.8597, -13.4469) (8.9498, -13.4935) (9.0407, -13.5392) (9.1325, -13.5837) (9.202, -13.6164) (9.2487, -13.6378) (9.2721, -13.6484) knots 0 0 0 0 0 0.03125 0.0625 0.09375 0.125 0.15625 0.1875 0.21875 0.25 0.28125 0.3125 0.34375 0.375 0.40625 0.4375 0.46875 0.5 0.53125 0.5625 0.59375 0.625 0.65625 0.6875 0.71875 0.75 0.78125 0.8125 0.84375 0.875 0.90625 0.9375 0.96875 1 1 1 1 1
  spline S35 degree 4 poles (10.1152, -13.0358) (10.1123, -13.0103) (10.1064, -12.9593) (10.0968, -12.8831) (10.0828, -12.782) (10.0675, -12.6814) (10.051, -12.5814) (10.0333, -12.482) (10.0144, -12.3833) (9.9944, -12.2854) (9.9731, -12.1884) (9.9506, -12.092) (9.9267, -11.9962) (9.9012, -11.9008) (9.8742, -11.806) (9.8459, -11.7122) (9.8165, -11.6196) (9.7863, -11.5288) (9.7549, -11.4393) (9.7218, -11.3505) (9.6861, -11.2615) (9.6477, -11.172) (9.6069, -11.0828) (9.5653, -10.9962) (9.5241, -10.9143) (9.4836, -10.838) (9.442, -10.7654) (9.3951, -10.6919) (9.3378, -10.6116) (9.2652, -10.5185) (9.1734, -10.4082) (9.0603, -10.278) (8.9243, -10.1262) (8.8049, -9.9957) (8.7175, -9.9013) (8.6718, -9.8522) knots 0 0 0 0 0 0.03125 0.0625 0.09375 0.125 0.15625 0.1875 0.21875 0.25 0.28125 0.3125 0.34375 0.375 0.40625 0.4375 0.46875 0.5 0.53125 0.5625 0.59375 0.625 0.65625 0.6875 0.71875 0.75 0.78125 0.8125 0.84375 0.875 0.90625 0.9375 0.96875 1 1 1 1 1
  spline S36 degree 4 poles (9.8522, -8.6718) (9.9012, -8.7174) (9.9956, -8.8047) (10.126, -8.924) (10.2777, -9.0598) (10.4079, -9.1728) (10.5181, -9.2645) (10.6112, -9.3371) (10.6916, -9.3944) (10.7651, -9.4414) (10.8377, -9.4831) (10.9141, -9.5236) (10.996, -9.5648) (11.0827, -9.6065) (11.1718, -9.6473) (11.2614, -9.6858) (11.3504, -9.7214) (11.4392, -9.7546) (11.5287, -9.786) (11.6196, -9.8163) (11.7121, -9.8456) (11.806, -9.874) (11.9008, -9.901) (11.9961, -9.9265) (12.092, -9.9505) (12.1884, -9.973) (12.2854, -9.9942) (12.3833, -10.0143) (12.482, -10.0332) (12.5814, -10.0509) (12.6814, -10.0674) (12.782, -10.0827) (12.8831, -10.0968) (12.9593, -10.1063) (13.0103, -10.1123) (13.0358, -10.1152) knots 0 0 0 0 0 0.03125 0.0625 0.09375 0.125 0.15625 0.1875 0.21875 0.25 0.28125 0.3125 0.34375 0.375 0.40625 0.4375 0.46875 0.5 0.53125 0.5625 0.59375 0.625 0.65625 0.6875 0.71875 0.75 0.78125 0.8125 0.84375 0.875 0.90625 0.9375 0.96875 1 1 1 1 1
  spline S37 degree 4 poles (13.6484, -9.2721) (13.6378, -9.2487) (13.6164, -9.202) (13.5837, -9.1325) (13.5391, -9.0407) (13.4935, -8.9497) (13.4468, -8.8597) (13.3992, -8.7706) (13.3508, -8.6826) (13.3014, -8.5957) (13.2512, -8.51) (13.2, -8.4252) (13.1476, -8.3415) (13.0939, -8.2587) (13.0389, -8.1769) (12.9829, -8.0963) (12.9264, -8.0174) (12.8695, -7.9403) (12.812, -7.8649) (12.753, -7.7907) (12.6916, -7.717) (12.6274, -7.6438) (12.561, -7.5716) (12.4946, -7.502) (12.4301, -7.4368) (12.3679, -7.3767) (12.3058, -7.3205) (12.2385, -7.2651) (12.1591, -7.2064) (12.0613, -7.1403) (11.9401, -7.0638) (11.7923, -6.9749) (11.6163, -6.8726) (11.4626, -6.7855) (11.3504, -6.7228) (11.2919, -6.6902) knots 0 0 0 0 0 0.03125 0.0625 0.09375 0.125 0.15625 0.1875 0.21875 0.25 0.28125 0.3125 0.34375 0.375 0.40625 0.4375 0.46875 0.5 0.53125 0.5625 0.59375 0.625 0.65625 0.6875 0.71875 0.75 0.78125 0.8125 0.84375 0.875 0.90625 0.9375 0.96875 1 1 1 1 1
  spline S38 degree 4 poles (12.0497, -5.2029) (12.1105, -5.2311) (12.2272, -5.285) (12.3881, -5.3581) (12.5744, -5.4403) (12.7332, -5.5076) (12.8664, -5.5607) (12.9774, -5.6011) (13.0715, -5.6307) (13.1559, -5.6527) (13.2379, -5.6699) (13.323, -5.6849) (13.4137, -5.6988) (13.5089, -5.7116) (13.6064, -5.7229) (13.7034, -5.7318) (13.7991, -5.7382) (13.8938, -5.7423) (13.9886, -5.7445) (14.0844, -5.7452) (14.1814, -5.7446) (14.2795, -5.7425) (14.378, -5.7389) (14.4766, -5.7337) (14.5751, -5.7269) (14.6737, -5.7185) (14.7726, -5.7087) (14.8719, -5.6975) (14.9715, -5.685) (15.0716, -5.6711) (15.1718, -5.6559) (15.2722, -5.6394) (15.3727, -5.6215) (15.4481, -5.607) (15.4984, -5.597) (15.5236, -5.5918) knots 0 0 0 0 0 0.03125 0.0625 0.09375 0.125 0.15625 0.1875 0.21875 0.25 0.28125 0.3125 0.34375 0.375 0.40625 0.4375 0.46875 0.5 0.53125 0.5625 0.59375 0.625 0.65625 0.6875 0.71875 0.75 0.78125 0.8125 0.84375 0.875 0.90625 0.9375 0.96875 1 1 1 1 1
  spline S39 degree 4 poles (15.8456, -4.6007) (15.8283, -4.5817) (15.7935, -4.544) (15.741, -4.4879) (15.6702, -4.4144) (15.5987, -4.342) (15.5265, -4.2708) (15.4537, -4.2008) (15.3804, -4.132) (15.3067, -4.0646) (15.2325, -3.9986) (15.1576, -3.9338) (15.0819, -3.8704) (15.0052, -3.8082) (14.9276, -3.7474) (14.8495, -3.6881) (14.7714, -3.6305) (14.6934, -3.5748) (14.6155, -3.5208) (14.5364, -3.4685) (14.4553, -3.4174) (14.3715, -3.3676) (14.2861, -3.3194) (14.2015, -3.2738) (14.12, -3.2318) (14.0423, -3.1938) (13.9659, -3.1595) (13.8847, -3.1277) (13.7912, -3.0963) (13.6777, -3.0637) (13.5387, -3.0284) (13.3707, -2.9895) (13.1717, -2.9466) (12.9985, -2.9113) (12.8723, -2.8863) (12.8066, -2.8734) knots 0 0 0 0 0 0.03125 0.0625 0.09375 0.125 0.15625 0.1875 0.21875 0.25 0.28125 0.3125 0.34375 0.375 0.40625 0.4375 0.46875 0.5 0.53125 0.5625 0.59375 0.625 0.65625 0.6875 0.71875 0.75 0.78125 0.8125 0.84375 0.875 0.90625 0.9375 0.96875 1 1 1 1 1
  arc A0 (16.4918, -0.5211) -> (16.4918, 0.5211) centre (0, 0) ccw
  arc A1 (13.0677, 1.2247) -> (12.8066, 2.8734) centre (0, 0) ccw
  arc A2 (15.8456, 4.6007) -> (15.5236, 5.5918) centre (0, 0) ccw
  arc A3 (12.0497, 5.2029) -> (11.2919, 6.6902) centre (0, 0) ccw
  arc A4 (13.6484, 9.2721) -> (13.0358, 10.1152) centre (0, 0) ccw
  arc A5 (9.8522, 8.6718) -> (8.6718, 9.8522) centre (0, 0) ccw
  arc A6 (10.1152, 13.0358) -> (9.2721, 13.6484) centre (0, 0) ccw
  arc A7 (6.6902, 11.2919) -> (5.2029, 12.0497) centre (0, 0) ccw
  arc A8 (5.5918, 15.5236) -> (4.6007, 15.8456) centre (0, 0) ccw
  arc A9 (2.8734, 12.8066) -> (1.2247, 13.0677) centre (0, 0) ccw
  arc A10 (0.5211, 16.4918) -> (-0.5211, 16.4918) centre (0, 0) ccw
  arc A11 (-1.2247, 13.0677) -> (-2.8734, 12.8066) centre (0, 0) ccw
  arc A12 (-4.6007, 15.8456) -> (-5.5918, 15.5236) centre (0, 0) ccw
  arc A13 (-5.2029, 12.0497) -> (-6.6902, 11.2919) centre (0, 0) ccw
  arc A14 (-9.2721, 13.6484) -> (-10.1152, 13.0358) centre (0, 0) ccw
  arc A15 (-8.6718, 9.8522) -> (-9.8522, 8.6718) centre (0, 0) ccw
  arc A16 (-13.0358, 10.1152) -> (-13.6484, 9.2721) centre (0, 0) ccw
  arc A17 (-11.2919, 6.6902) -> (-12.0497, 5.2029) centre (0, 0) ccw
  arc A18 (-15.5236, 5.5918) -> (-15.8456, 4.6007) centre (0, 0) ccw
  arc A19 (-12.8066, 2.8734) -> (-13.0677, 1.2247) centre (0, 0) ccw
  arc A20 (-16.4918, 0.5211) -> (-16.4918, -0.5211) centre (0, 0) ccw
  arc A21 (-13.0677, -1.2247) -> (-12.8066, -2.8734) centre (0, 0) ccw
  arc A22 (-15.8456, -4.6007) -> (-15.5236, -5.5918) centre (0, 0) ccw
  arc A23 (-12.0497, -5.2029) -> (-11.2919, -6.6902) centre (0, 0) ccw
  arc A24 (-13.6484, -9.2721) -> (-13.0358, -10.1152) centre (0, 0) ccw
  arc A25 (-9.8522, -8.6718) -> (-8.6718, -9.8522) centre (0, 0) ccw
  arc A26 (-10.1152, -13.0358) -> (-9.2721, -13.6484) centre (0, 0) ccw
  arc A27 (-6.6902, -11.2919) -> (-5.2029, -12.0497) centre (0, 0) ccw
  arc A28 (-5.5918, -15.5236) -> (-4.6007, -15.8456) centre (0, 0) ccw
  arc A29 (-2.8734, -12.8066) -> (-1.2247, -13.0677) centre (0, 0) ccw
  arc A30 (-0.5211, -16.4918) -> (0.5211, -16.4918) centre (0, 0) ccw
  arc A31 (1.2247, -13.0677) -> (2.8734, -12.8066) centre (0, 0) ccw
  arc A32 (4.6007, -15.8456) -> (5.5918, -15.5236) centre (0, 0) ccw
  arc A33 (5.2029, -12.0497) -> (6.6902, -11.2919) centre (0, 0) ccw
  arc A34 (9.2721, -13.6484) -> (10.1152, -13.0358) centre (0, 0) ccw
  arc A35 (8.6718, -9.8522) -> (9.8522, -8.6718) centre (0, 0) ccw
  arc A36 (13.0358, -10.1152) -> (13.6484, -9.2721) centre (0, 0) ccw
  arc A37 (11.2919, -6.6902) -> (12.0497, -5.2029) centre (0, 0) ccw
  arc A38 (15.5236, -5.5918) -> (15.8456, -4.6007) centre (0, 0) ccw
  arc A39 (12.8066, -2.8734) -> (13.0677, -1.2247) centre (0, 0) ccw
  point P0 (14.0401, -1.3073)
  point P1 (14.3864, -1.2883)
  point P2 (14.7362, -1.2256)
  point P3 (15.0875, -1.1326)
  point P4 (15.4396, -1.0136)
  point P5 (15.7914, -0.8711)
  point P6 (16.1424, -0.7066)
  point P7 (16.141, 0.7085)
  point P8 (15.7889, 0.8746)
  point P9 (15.4361, 1.0185)
  point P10 (15.0834, 1.1385)
  point P11 (14.7314, 1.2322)
  point P12 (14.3812, 1.2954)
  point P13 (14.0346, 1.3145)
  point P14 (13.7534, 3.0865)
  point P15 (14.077, 3.2119)
  point P16 (14.3906, 3.3803)
  point P17 (14.6964, 3.5783)
  point P18 (14.9949, 3.8015)
  point P19 (15.2861, 4.0473)
  point P20 (15.5698, 4.3141)
  point P21 (15.1321, 5.6616)
  point P22 (14.746, 5.7108)
  point P23 (14.366, 5.7386)
  point P24 (13.9934, 5.7437)
  point P25 (13.6297, 5.7241)
  point P26 (13.2771, 5.6759)
  point P27 (12.9415, 5.5869)
  point P28 (12.1268, 7.1854)
  point P29 (12.3959, 7.4046)
  point P30 (12.642, 7.6616)
  point P31 (12.8717, 7.9444)
  point P32 (13.0866, 8.2489)
  point P33 (13.2875, 8.5727)
  point P34 (13.4747, 8.9142)
  point P35 (12.6422, 10.0606)
  point P36 (12.2599, 9.988)
  point P37 (11.8902, 9.8969)
  point P38 (11.5344, 9.7866)
  point P39 (11.1946, 9.6555)
  point P40 (10.8742, 9.5007)
  point P41 (10.5826, 9.3123)
  point P42 (9.3126, 10.581)
  point P43 (9.5009, 10.8727)
  point P44 (9.6556, 11.1932)
  point P45 (9.7866, 11.5332)
  point P46 (9.8969, 11.8892)
  point P47 (9.988, 12.2592)
  point P48 (10.0606, 12.6418)
  point P49 (8.9141, 13.4748)
  point P50 (8.5726, 13.2877)
  point P51 (8.2487, 13.0868)
  point P52 (7.9442, 12.8719)
  point P53 (7.6614, 12.6423)
  point P54 (7.4044, 12.396)
  point P55 (7.1853, 12.1267)
  point P56 (5.5874, 12.9407)
  point P57 (5.6764, 13.2763)
  point P58 (5.7245, 13.629)
  point P59 (5.7441, 13.9928)
  point P60 (5.7389, 14.3655)
  point P61 (5.7111, 14.7456)
  point P62 (5.6618, 15.1319)
  point P63 (4.3139, 15.57)
  point P64 (4.047, 15.2864)
  point P65 (3.8011, 14.9953)
  point P66 (3.5779, 14.6969)
  point P67 (3.3799, 14.391)
  point P68 (3.2117, 14.0774)
  point P69 (3.0864, 13.7536)
  point P70 (1.3151, 14.0339)
  point P71 (1.2961, 14.3806)
  point P72 (1.2329, 14.7309)
  point P73 (1.1391, 15.0829)
  point P74 (1.019, 15.4358)
  point P75 (0.875, 15.7887)
  point P76 (0.7087, 16.1409)
  point P77 (-0.7087, 16.141)
  point P78 (-0.8751, 15.7888)
  point P79 (-1.019, 15.4359)
  point P80 (-1.1391, 15.0831)
  point P81 (-1.233, 14.731)
  point P82 (-1.2961, 14.3807)
  point P83 (-1.3151, 14.034)
  point P84 (-3.0859, 13.7536)
  point P85 (-3.2111, 14.0774)
  point P86 (-3.3794, 14.391)
  point P87 (-3.5775, 14.6968)
  point P88 (-3.8007, 14.9953)
  point P89 (-4.0467, 15.2864)
  point P90 (-4.3138, 15.5699)
  point P91 (-5.6619, 15.132)
  point P92 (-5.7113, 14.7456)
  point P93 (-5.7391, 14.3655)
  point P94 (-5.7443, 13.9928)
  point P95 (-5.7248, 13.629)
  point P96 (-5.6766, 13.2764)
  point P97 (-5.5875, 12.9408)
  point P98 (-7.1849, 12.1268)
  point P99 (-7.404, 12.396)
  point P100 (-7.661, 12.6423)
  point P101 (-7.9439, 12.8719)
  point P102 (-8.2485, 13.0868)
  point P103 (-8.5724, 13.2877)
  point P104 (-8.914, 13.4748)
  point P105 (-10.0608, 12.6417)
  point P106 (-9.9883, 12.2591)
  point P107 (-9.8974, 11.889)
  point P108 (-9.7872, 11.5329)
  point P109 (-9.6561, 11.193)
  point P110 (-9.5013, 10.8725)
  point P111 (-9.3129, 10.5808)
  point P112 (-10.5806, 9.3129)
  point P113 (-10.8723, 9.5013)
  point P114 (-11.1928, 9.6561)
  point P115 (-11.5328, 9.7871)
  point P116 (-11.8889, 9.8973)
  point P117 (-12.259, 9.9883)
  point P118 (-12.6417, 10.0607)
  point P119 (-13.4749, 8.9141)
  point P120 (-13.2877, 8.5727)
  point P121 (-13.0869, 8.2488)
  point P122 (-12.872, 7.9443)
  point P123 (-12.6423, 7.6615)
  point P124 (-12.3961, 7.4046)
  point P125 (-12.1267, 7.1855)
  point P126 (-12.9408, 5.5873)
  point P127 (-13.2763, 5.6763)
  point P128 (-13.629, 5.7245)
  point P129 (-13.9928, 5.744)
  point P130 (-14.3655, 5.7389)
  point P131 (-14.7456, 5.7111)
  point P132 (-15.132, 5.6618)
  point P133 (-15.57, 4.3139)
  point P134 (-15.2865, 4.047)
  point P135 (-14.9954, 3.8011)
  point P136 (-14.6969, 3.5779)
  point P137 (-14.3911, 3.3799)
  point P138 (-14.0775, 3.2116)
  point P139 (-13.7536, 3.0865)
  point P140 (-14.034, 1.3148)
  point P141 (-14.3807, 1.2958)
  point P142 (-14.731, 1.2326)
  point P143 (-15.083, 1.1388)
  point P144 (-15.4359, 1.0187)
  point P145 (-15.7888, 0.8748)
  point P146 (-16.1409, 0.7086)
  point P147 (-16.1409, -0.7085)
  point P148 (-15.7888, -0.8747)
  point P149 (-15.4359, -1.0185)
  point P150 (-15.083, -1.1385)
  point P151 (-14.731, -1.2323)
  point P152 (-14.3807, -1.2955)
  point P153 (-14.034, -1.3146)
  point P154 (-13.7535, -3.0859)
  point P155 (-14.0773, -3.2111)
  point P156 (-14.3909, -3.3795)
  point P157 (-14.6967, -3.5775)
  point P158 (-14.9952, -3.8008)
  point P159 (-15.2863, -4.0468)
  point P160 (-15.5699, -4.3138)
  point P161 (-15.132, -5.6618)
  point P162 (-14.7456, -5.7111)
  point P163 (-14.3655, -5.7389)
  point P164 (-13.9929, -5.7441)
  point P165 (-13.629, -5.7245)
  point P166 (-13.2764, -5.6764)
  point P167 (-12.9408, -5.5873)
  point P168 (-12.1273, -7.1859)
  point P169 (-12.3965, -7.4049)
  point P170 (-12.6427, -7.6617)
  point P171 (-12.8723, -7.9445)
  point P172 (-13.0871, -8.2489)
  point P173 (-13.2879, -8.5727)
  point P174 (-13.475, -8.9142)
  point P175 (-12.6417, -10.0604)
  point P176 (-12.259, -9.9877)
  point P177 (-11.8889, -9.8966)
  point P178 (-11.5329, -9.7863)
  point P179 (-11.1929, -9.6554)
  point P180 (-10.8724, -9.5009)
  point P181 (-10.5807, -9.3131)
  point P182 (-9.3128, -10.5822)
  point P183 (-9.5013, -10.8737)
  point P184 (-9.6561, -11.1941)
  point P185 (-9.7871, -11.5339)
  point P186 (-9.8974, -11.8898)
  point P187 (-9.9883, -12.2596)
  point P188 (-10.0608, -12.642)
  point P189 (-8.914, -13.4749)
  point P190 (-8.5724, -13.2878)
  point P191 (-8.2485, -13.087)
  point P192 (-7.9439, -12.8721)
  point P193 (-7.6611, -12.6425)
  point P194 (-7.4041, -12.3962)
  point P195 (-7.185, -12.1269)
  point P196 (-5.5873, -12.9423)
  point P197 (-5.6764, -13.2777)
  point P198 (-5.7247, -13.6302)
  point P199 (-5.7442, -13.9938)
  constraints: 80 point on circle, 40 centre point, 360 other
extrude "Extrusão2" add sketch "Esboço2" along normal blind 15
sketch "Esboço3" plane through (0, 0, 0) normal (0, 0, 1) x (1, 0, 0)
  circle A0 centre (0, 0) radius 6
  dimension "d6" = 12
  constraints: 1 centre point
  measures "d6" diameter of A0
extrude "Extrusão3" cut sketch "Esboço3" along normal through all
equation "\"d0\" = diam_cubo"
equation "\"d1\" = esp_cubo"
equation "\"d4\" = larg_dentada"
equation "\"d6\" = furo"
equation "\"furo\" = 12"
equation "\"diam_cubo\" = 20"
equation "\"esp_cubo\" = 20"
equation "\"larg_dentada\" = 15"
equation "\"folga_dentes\" = 2.5"
equation "\"d3\" = folga_dentes"
